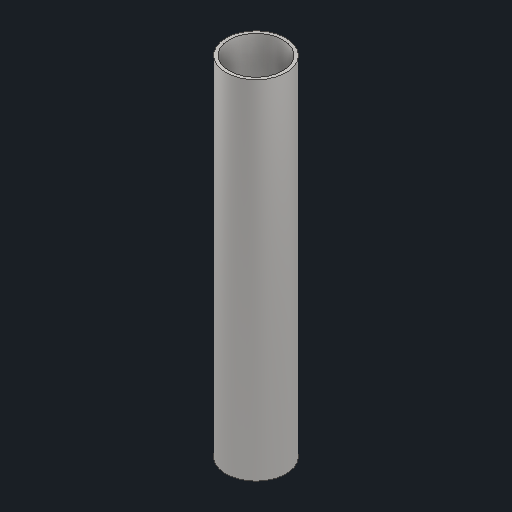
# Autodesk Inventor part: tripod_leg_inner
Saved by Autodesk Inventor 2027.1 (Build 311270010, 270A)
## iProperties
Created: 2026-11-04
Part Number: tripod_leg_inner
Material: Generic
Description: 1.5 in stainless extension leg (shown mostly retracted, as in the photo)
Document SubType Name: Modeling
Designer: Claude (from photos)
Density: 1 g/cm^3
Appearance: Stainless - Satin
Author: alexg
Autodesk Inventor part; units mm, degrees
ref_plane "YZ Plane" through (0, 0, 0) normal (1, 0, 0) x (0, 1, 0)
ref_plane "XY Plane" through (0, 0, 0) normal (0, 0, 1) x (1, 0, 0)
ref_plane "Work Plane1" through (0, -560, 0) normal (0, 1, 0) x (-1, 0, 0)
sketch "Extension leg 1.5in sketch" plane through (0, -560, 0) normal (0, 1, 0) x (-1, 0, 0)
  circle A0 centre (0, 0) radius 19
  circle A1 centre (0, 0) radius 17
  constraints: 2 centre point
extrude "Extension leg 1.5in" add sketch "Extension leg 1.5in sketch" against normal blind 220
body "Solid1"
